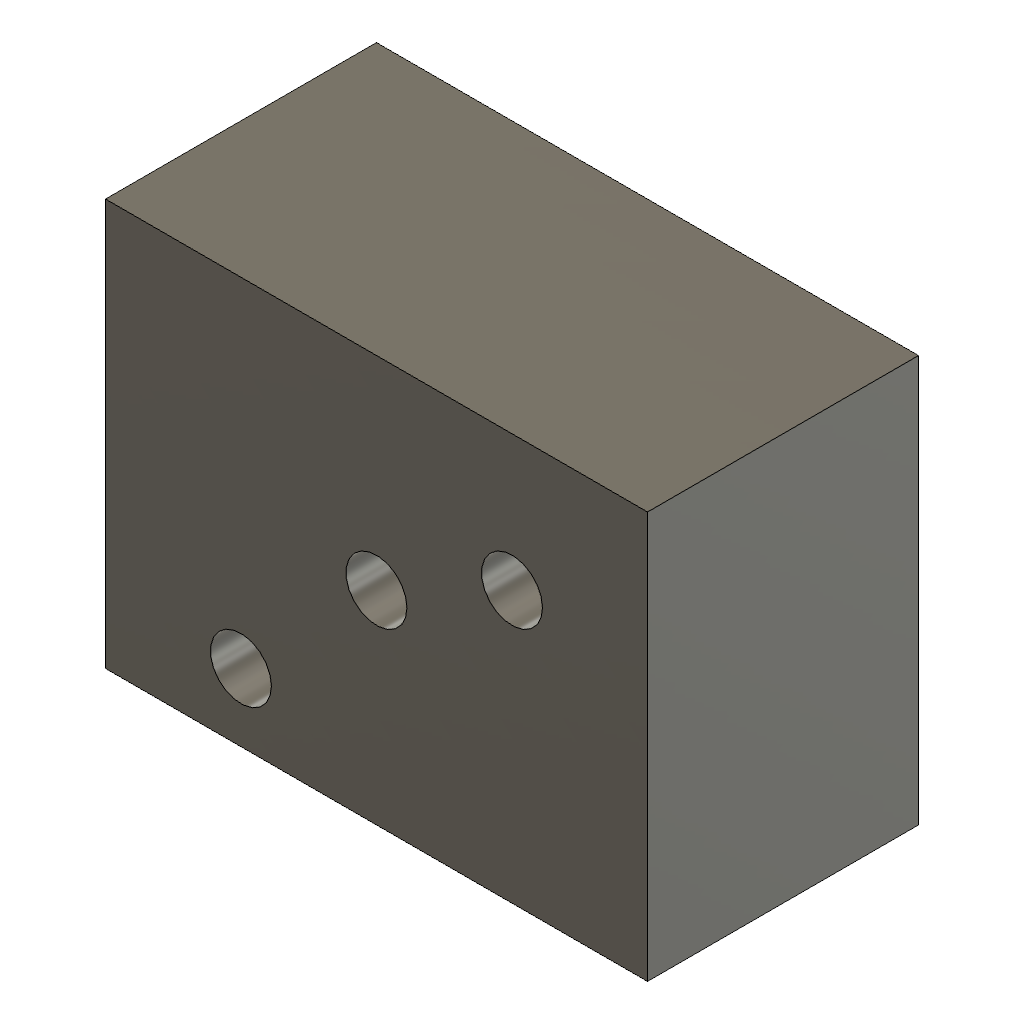
sketch_points (Autodesk Fusion 360 design; units mm, degrees)
part number: 2026-10-20-19-38-30-220
Autodesk Fusion 360 part; units mm, degrees
sketch "Sketch1" plane through (0, 0, 0) normal (0, 0, 1) x (1, 0, 0)
  line L0 (10, 10) -> (50, 10)
  line L1 (50, 10) -> (50, 40)
  line L2 (50, 40) -> (10, 40)
  line L3 (10, 40) -> (10, 10)
extrude "Extrude1" add sketch "Sketch1" along normal blind 20
sketch "HoleLocations" plane through (0, 0, 20) normal (0, 0, 1) x (1, 0, 0)
  line L0 (10, 40) -> (10, 10)
  line L1 (10, 10) -> (50, 10)
  line L2 (50, 10) -> (50, 40)
  line L3 (50, 40) -> (10, 40)
  point P0 (20, 15)
  point P1 (30, 25)
  point P2 (40, 30)
hole "ProbeHolePlacement" at (20, 15, 20) at (30, 25, 20) at (40, 30, 20) direction (0, 0, -1) diameter 4.5 depth 11 tip angle 118
